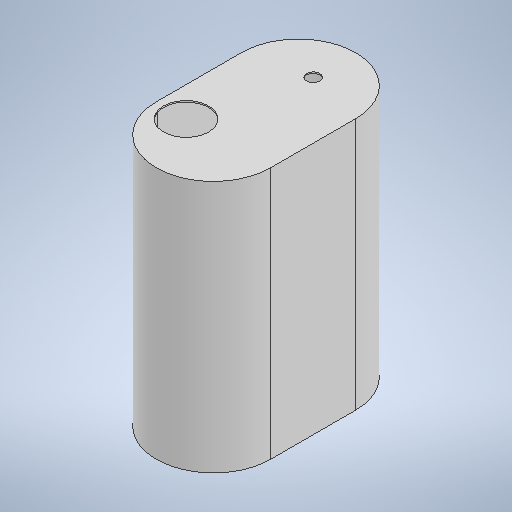
# Autodesk Inventor part: RDS-1001 Tank 2m3 Parfino
Saved by Autodesk Inventor 2026.2 (Build 302298000, 298)
## iProperties
Created: 2026-10-12
Part Number: RDS-1001 Tank 2m3 Parfino
Material: Generic
Description: Tank 2 m3 Parfino, obround 1500x860 H1900, wall 10
Document SubType Name: Modeling
Designer: admin
Stock Number: Емкость 2 м3 Парфино (ПЭ), овал 1500х860, H1900
Mass: 95905.8 g
Surface Area: 191956 cm^2
Volume: 95905.8 cm^3
Density: 1 g/cm^3
Appearance: Default
Author: admin
Autodesk Inventor part; units mm, degrees
ref_plane "YZ Plane" through (0, 0, 0) normal (1, 0, 0) x (0, 1, 0)
ref_plane "XZ Plane" through (0, 0, 0) normal (0, 1, 0) x (-1, 0, 0)
ref_plane "XY Plane" through (0, 0, 0) normal (0, 0, 1) x (1, 0, 0)
sketch "Sketch1" plane through (0, 0, 0) normal (0, 1, 0) x (-1, 0, 0)
  line L0 (-430, -320) -> (-430, 320)
  line L1 (430, 320) -> (430, -320)
  arc A0 (430, 320) -> (-430, 320) centre (0, 320) ccw
  arc A1 (-430, -320) -> (430, -320) centre (0, -320) ccw
  dimension "d0" = 430
  dimension "d1" = 640
  constraints: 4 end point, 4 point on circle, 4 tangent, 2 centre point, 1 equal radius
  measures "d0" radius of A0
  measures "d1" distance of L0.start L0.end
extrude "Extrusion1" add sketch "Sketch1" along normal blind 1900
shell "Shell1" thickness 10 removed faces 0
sketch "Sketch3" plane through (0, 1900, 0) normal (0, 1, 0) x (1, 0, 0)
  circle A0 centre (0, 430) radius 50
  circle A1 centre (-206, -320) radius 170
  dimension "d10" = 100
  dimension "d11" = 340
  constraints: 2 centre point
  measures "d10" diameter of A0
  measures "d11" diameter of A1
extrude "Extrusion3" cut sketch "Sketch3" along normal mid plane 40
equation "\"d0\" = 0.5 * Tank01_Width"
equation "\"d1\" = Tank01_Length - Tank01_Width"
equation "\"d2\" = Tank01_Height"
equation "\"d4\" = Tank01_Wall_Thickness"
equation "\"d10\" = Tank01_Mixer_Hole_Diam"
equation "\"d11\" = Tank01_Hatch_Diam"
equation "\"d12\" = 4 * Tank01_Wall_Thickness"
equation "\"Tank01_Length\" = 1500"
equation "\"Tank01_Width\" = 860"
equation "\"Tank01_Height\" = 1900"
equation "\"Tank01_Wall_Thickness\" = 10"
equation "\"Tank01_Mixer_Hole_Diam\" = 100"
equation "\"Tank01_Hatch_Diam\" = 340"
body "Solid1"
